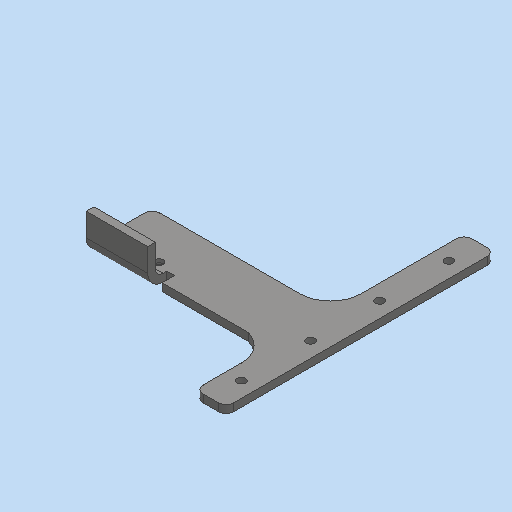
# Autodesk Inventor part: MM0861AN200_G22_216
Saved by Autodesk Inventor 2023.3 (Build 273359000, 359)
## iProperties
Part Number: MM0861AN200_G22_216
Material: 1.4301 X5CrNi18-10
Description: =<RBPARTNOTITLE2>
Document SubType Name: Blech
Designer: Benutzer
Mass: 343.196 g
Surface Area: 213.075 cm^2
Volume: 43.7192 cm^3
Density: 7.85 g/cm^3
Sheet Metal Rule: Standard_mm
Appearance: Stahl - rostfrei AnP
Vendor: ASW
Flat Pattern Width: 13.6 cm
Flat Pattern Length: 17.5 cm
Flat Pattern Area: 238 cm^2
Sheet Metal Width: 136,000 mm
Sheet Metal Length: 175,000 mm
Sheet Metal Area: 23800,000 mm^2
RBCHANGEDESCRIPTION1: Erstfreigabe
RBCHANGENO1: 00
RBDOCUMENTTYPE: DRF
RBDOCUMENTVERSION: 00
RBDRAWINGMAINSCALE: 1:1
RBDRAWINGMISSINGSPEC: --
RBDRAWINGVOLUME: --
RBDSV1: 0850
RBGBDETAILS: 43274
RBGBEDGESIN1: +0,5
RBGBEDGESIN2: +0,2
RBGBEDGESOUT1: -0,3
RBGBEDGESOUT2: -0,1
RBMATERIAL: =<Material>
RBMATMEETS: --
RBMATNO: =<Part Number>
RBORGUNITRESPONSIBLE1: AnP/TEF1
RBPARTMADEOF: 5 x 75 x 136 (FM)
RBPARTNO: SIEHE MNR
RBPARTNOTITLE1: manufactured part
RBPARTNOTITLE2: Anfertigungsteil
RBPARTSAFETYINDICATOR: --
RBSURFACE: --
RBSURFACE2: --
RBZEDGESNORM: ISO13715:2002-06
RBZGENDIMCLASS: m
RBZGENDIMNORM: ISO 2768-1:1989-11
RBZGENGEOCLASS: H
RBZGENGEONORM: ISO 2768-2:1989-11
RBZSURFACENORM: ISO13D2:2002-02
RBZTOLERANCENORM: ISO 14405-1:2010-12
AnP_Material: =<Material>
AnP_TemplVers: 20190222
AnP_Kategorie: 1
MaxAbmaße: 5 x 75 x 136 (FM)
Author: Benutzer
Keywords: =<RBPARTMADEOF>
Comments: =<RBSURFACE2>
Revision Number: 01
Autodesk Inventor part; units mm, degrees
ref_plane "YZ Plane" through (0, 0, 0) normal (1, 0, 0) x (0, 1, 0)
ref_plane "XZ Plane" through (0, 0, 0) normal (0, 1, 0) x (-1, 0, 0)
ref_plane "XY Plane" through (0, 0, 0) normal (0, 0, 1) x (1, 0, 0)
sketch "Skizze1" plane through (0, 0, 0) normal (0, 0, 1) x (1, 0, 0)
  line L0 (0, 0) -> (136, 0)
  line L1 (136, 0) -> (136, 75)
  line L2 (136, 75) -> (0, 75)
  line L3 (0, 75) -> (0, 0)
  dimension "d0" = 136
  dimension "d1" = 75
  constraints: 8 end point, 2 parallel, 1 horizontal, 1 perpendicular
  measures "d0" distance between parallel lines of L1 L3
  measures "d1" distance of L0.end L1.end
extrude "Extrusion1" add sketch "Skizze1" along normal blind 5
sketch "Skizze2" plane through (0, 0, 5) normal (0, 0, 1) x (1, 0, 0)
  line L0 (0, 0) -> (136, 0) projected
  line L1 (136, 0) -> (136, 75) projected
  line L2 (136, 75) -> (0, 75) projected
  line L3 (0, 75) -> (0, 0) projected
  line L4 (0, 30) -> (100, 30)
  line L5 (100, 30) -> (116, 30)
  line L6 (116, 30) -> (116, 75)
  dimension "d4" = 30
  dimension "d6" = 20
  constraints: 6 end point, 3 point on line, 1 horizontal, 1 perpendicular
  measures "d4" distance from line of L4.start L0
  measures "d6" distance of L1.end L6.end
extrude "Extrusion2" cut sketch "Skizze2" against normal through all contours L3 L2 L6 L5 L4
sketch "Skizze3" plane through (0, 0, 5) normal (0, 0, 1) x (1, 0, 0)
  line L0 (0, 0) -> (136, 0) projected
  line L1 (0, 30) -> (0, 0) projected
  point P0 (7.5, 10)
  point P1 (32.5, 10)
  dimension "d10" = 25
  dimension "d11" = 10
  dimension "d12" = 7.5
  constraints: 1 horizontal alignment
  measures "d10" distance of point (32.5, 10) point (7.5, 10)
  measures "d11" distance from line of L0 point (7.5, 10)
  measures "d12" distance from line of point (7.5, 10) L1
hole "Bohrung1" at (7.5, 10, 5) at (32.5, 10, 5) direction (0, 0, -1) diameter 5.5 end through all countersink diameter 11 countersink angle 90
sketch "Skizze5" plane through (0, 0, 5) normal (0, 0, 1) x (1, 0, 0)
  line L0 (136, 0) -> (136, 75) projected
  line L1 (136, 75) -> (116, 75) projected
  line L2 (0, 0) -> (136, 0) projected
  point P0 (126, 60)
  point P1 (126, 15)
  dimension "d34" = 10
  dimension "d35" = 15
  dimension "d36" = 15
  constraints: 1 vertical alignment
  measures "d34" distance from line of L0 point (126, 60)
  measures "d35" distance from line of point (126, 60) L1
  measures "d36" distance from line of L2 point (126, 15)
hole "Bohrung2" at (126, 60, 5) at (126, 15, 5) direction (0, 0, -1) diameter 5.5 depth 5 tip angle 118
sketch "Skizze6" plane through (0, 0, 0) normal (0, -1, 0) x (1, 0, 0)
  line L0 (0, 0) -> (136, 0) projected
  line L1 (136, 0) -> (136, 5) projected
  line L2 (0, 5) -> (136, 5) projected
  line L3 (0, 0) -> (0, 5) projected
  line L4 (136, 0) -> (116, 0)
  line L5 (116, 0) -> (116, 5)
  line L6 (116, 5) -> (136, 5)
  line L7 (136, 5) -> (136, 0)
  dimension "d45" = 20
  constraints: 8 end point, 2 parallel, 1 horizontal, 1 perpendicular, 1 point on line
  measures "d45" distance between parallel lines of L1 L5
extrude "Extrusion4" add sketch "Skizze6" along normal blind 50 contours L5 L2 L1 L0
sketch "Skizze7" plane through (136, 75, 5) normal (0, 1, 0) x (1, 0, 0)
  line L0 (-20, 5) -> (-20, 0) projected
  line L1 (0, 0) -> (-20, 0) projected
  line L2 (0, 5) -> (0, 0) projected
  line L3 (0, 5) -> (-20, 5) projected
  point P0 (-136, 5)
extrude "Extrusion5" add sketch "Skizze7" along normal blind 50
sketch "Skizze8" plane through (0, 0, 0) normal (0, 0, -1) x (-1, 0, 0)
  circle A0 centre (-126, 60) radius 2.75 projected
  circle A1 centre (-126, 15) radius 2.75 projected
  point P0 (0, 0)
  point P1 (-126, 105)
  point P2 (-126, -30)
  dimension "d51" = 45
  dimension "d59" = 135
  constraints: 2 vertical alignment
  measures "d51" distance of point (-126, -30) A1.centre
  measures "d59" distance of point (-126, 105) point (-126, -30)
hole "Bohrung3" at (126, 105, 0) at (126, -30, 0) direction (0, 0, 1) diameter 5.5 depth 5 tip angle 118
fillet "Rundung3" radius 20 1 edges at (116, 0, 2.5)
sketch "Skizze10" plane through (0, 0, 0) normal (0, -1, 0) x (1, 0, 0)
  line L0 (96, 0) -> (0, 0)
  line L1 (0, 0) -> (0, -20)
  line L2 (0, -20) -> (96, -20)
  line L3 (96, -20) -> (96, 0)
  constraints: 6 end point, 1 horizontal, 1 perpendicular, 1 vertical
edge flange "Lasche2" height 25 angle 90 thickness 5 bend radius 5 thickness toward (0, -1, 0) relief straight relief width 5 relief depth 2.5 edges at (48, 0, 0) wall of the first edge with corners at (96, 0, 0) (0, 0, 0) (0, 0, -20) (96, 0, -20)
bend "Biegung2"
corner "Ecke2"
sketch "Skizze11" plane through (96, -5, -20) normal (1, 0, 0) x (0, 0, -1)
  line L0 (-15, 0) -> (-15, 5) projected
  arc A0 (-25, 10) -> (-15, 0) centre (-15, 10) ccw projected
  line L1 (-20, 10) -> (-25, 10) projected
  arc A1 (-20, 10) -> (-15, 5) centre (-15, 10) ccw projected
  line L2 (-15, 5) -> (0, 5) projected
  line L3 (0, 5) -> (0, 0) projected
  line L4 (0, 0) -> (-15, 0) projected
  line L5 (-15, 0) -> (-15, 5) projected
  line L6 (-15, 5) -> (0, 5) projected
  line L7 (0, 5) -> (0, 0) projected
  line L8 (0, 0) -> (-15, 0) projected
  arc A2 (-25, 10) -> (-15, 0) centre (-15, 10) ccw projected
  line L9 (-20, 10) -> (-25, 10) projected
  arc A3 (-20, 10) -> (-15, 5) centre (-15, 10) ccw projected
  line L10 (-20, 10) -> (-25, 10) projected
  line L11 (-25, 35) -> (-25, 10) projected
  line L12 (-25, 35) -> (-20, 35) projected
  line L13 (-20, 35) -> (-20, 10) projected
  line L14 (-20, 12.6328) -> (-25, 12.6328)
  point P0 (-20, 5)
  point P1 (-20, 10)
  constraints: 2 end point, 2 point on line, 1 perpendicular
extrude "Extrusion6" cut sketch "Skizze11" against normal blind 56 contours A0 L1 A1 L0 | L0 L2 L3 L4 | L11 L14 L13 L1
sketch "Skizze14" plane through (96, 7.6328, 0) normal (0, -1, 0) x (1, 0, 0)
  line L0 (0, 0) -> (0, 5) projected
  line L1 (-56, 5) -> (0, 5) projected
  line L2 (-56, 5) -> (-56, 0) projected
  line L3 (0, 0) -> (-56, 0) projected
  point P0 (-96, 0)
extrude "Extrusion7" add sketch "Skizze14" along normal up to surface (0.1328 mm away)
sketch "Skizze15" plane through (101, -0.6351, 5) normal (-1, 0, 0) x (0, 0, 1)
  line L0 (0, 8.1351) -> (0, 0) projected
  line L1 (-5, 8.1351) -> (0, 8.1351) projected
  line L2 (-5, 0) -> (-5, 8.1351) projected
  line L3 (0, 0) -> (-5, 0) projected
  point P0 (-5, 0.6351)
extrude "Extrusion8" add sketch "Skizze15" along normal blind 56
sketch "Skizze16" plane through (0, 30, 5) normal (0, 1, 0) x (1, 0, 0)
  line L0 (0, 5) -> (116, 5) projected
  line L1 (0, 0) -> (0, 5) projected
  line L2 (116, 0) -> (0, 0) projected
  line L3 (116, 0) -> (116, 5) projected
  point P0 (0, 5)
extrude "Extrusion9" add sketch "Skizze16" along normal blind 8
fillet "Rundung6" radius 20 1 edges at (116, 38, 2.5)
fillet "Rundung7" radius 5 5 edges at (0, 38, 2.5) (116, -50, 2.5) (136, -50, 2.5) (116, 125, 2.5) (136, 125, 2.5)
ref_plane "Arbeitsebene1" through (0, 0, 105) normal (0, 0, 1) x (1, 0, 0)
mirror "Spiegeln1" about plane through (0, 0, 105) normal (0, 0, 1) remove original yes
equation "\"d18\" = Stärke"
equation "\"d42\" = Stärke"
equation "\"d57\" = Stärke"
equation "\"d62\" = Stärke"
equation "\"d73\" = BreiteBiegungsfreistellung"
equation "\"d74\" = TiefeBiegungsfreistellung"
equation "\"d75\" = MinimalRest"
equation "\"d76\" = Übergangsradius"
equation "\"d79\" = Biegeradius"
equation "\"d80\" = GrößeEckenfreistellung"
equation "\"d81\" = Abstandsgröße"
equation "\"d82\" = JacobiRadiusGröße"
equation "\"Biegeradius\" = Stärke"
equation "\"BreiteBiegungsfreistellung\" = Stärke"
equation "\"TiefeBiegungsfreistellung\" = 0.5 * Stärke"
equation "\"Übergangsradius\" = Biegeradius"
equation "\"JacobiRadiusGröße\" = Biegeradius"
equation "\"Abstandsgröße\" = Stärke"
equation "\"Stärke\" = 5"
equation "\"MinimalRest\" = 10"
equation "\"GrößeEckenfreistellung\" = 20"
